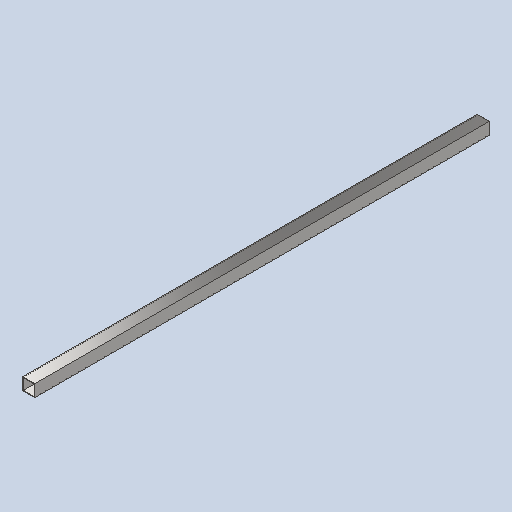
# Autodesk Inventor part: RDS-1301 Tube 40x40 L1500
Saved by Autodesk Inventor 2026.2 (Build 302298000, 298)
## iProperties
Created: 2026-10-18
Part Number: RDS-1301 Tube 40x40 L1500
Material: Stainless Steel, Austenitic
Description: Tank frame rail, AISI 304
Document SubType Name: Modeling
Designer: admin
Stock Number: Труба 40х40х2 L1500 — продольная рамы на ёмкости
Density: 8 g/cm^3
Appearance: Semi-Polished
Author: admin
Autodesk Inventor part; units mm, degrees
ref_plane "YZ Plane" through (0, 0, 0) normal (1, 0, 0) x (0, 1, 0)
ref_plane "XZ Plane" through (0, 0, 0) normal (0, 1, 0) x (-1, 0, 0)
ref_plane "XY Plane" through (0, 0, 0) normal (0, 0, 1) x (1, 0, 0)
sketch "Sketch1" plane through (0, 0, 0) normal (0, 0, 1) x (1, 0, 0)
  line L0 (-20, -20) -> (20, -20)
  line L1 (20, -20) -> (20, 20)
  line L2 (20, 20) -> (-20, 20)
  line L3 (-20, 20) -> (-20, -20)
  line L4 (-18, -18) -> (18, -18)
  line L5 (18, -18) -> (18, 18)
  line L6 (18, 18) -> (-18, 18)
  line L7 (-18, 18) -> (-18, -18)
  constraints: 16 end point, 4 parallel, 2 horizontal, 2 perpendicular
extrude "Extrusion1" add sketch "Sketch1" along normal blind 1500
equation "\"d0\" = Tube1301_Length"
equation "\"Tube1301_Length\" = 1500"
equation "\"Tube1301_Wall_Thickness\" = 2"
body "Solid1"
